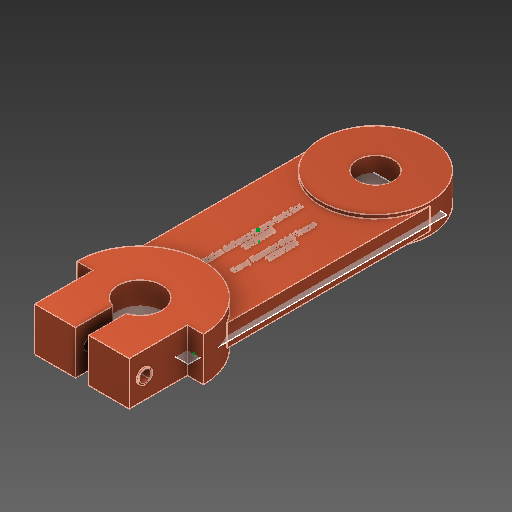
# Autodesk Inventor part: Brazo
Saved by Autodesk Inventor 2026.1 (Build 301233020, 233B)
## iProperties
Created: 2026-10-30
Part Number: Brazo
Material: Copper, Alloy
Document SubType Name: Modeling
Designer: YmCris
Density: 8.92 g/cm^3
Appearance: Copper - Satin
Author: YmCris
Autodesk Inventor part; units mm, degrees
(part 1 of 3)
ref_plane "YZ Plane" through (0, 0, 0) normal (1, 0, 0) x (0, 1, 0)
ref_plane "XZ Plane" through (0, 0, 0) normal (0, 1, 0) x (-1, 0, 0)
ref_plane "XY Plane" through (0, 0, 0) normal (0, 0, 1) x (1, 0, 0)
sketch "Sketch1" plane through (0, 0, 0) normal (0, 0, 1) x (1, 0, 0)
  point P0 (0, 0)
sketch "Sketch2" plane through (0, 0, 0) normal (0, 1, 0) x (-1, 0, 0)
  line L0 (-37.5, -80.915) -> (37.5, -80.915)
  line L1 (37.5, -80.915) -> (37.5, 80.915)
  line L2 (37.5, 80.915) -> (-37.5, 80.915)
  line L3 (-37.5, 80.915) -> (-37.5, -80.915)
  line L4 (-37.5, -80.915) -> (37.5, 80.915) construction
  line L5 (37.5, -80.915) -> (-37.5, 80.915) construction
  point P0 (0, 0)
  dimension "d4" = 75
  dimension "d5" = 161.83
  constraints: 12 end point, 2 midpoint, 2 parallel, 1 horizontal, 1 perpendicular
  measures "d4" distance of L2.end L1.end
  measures "d5" distance of L1.end L0.end
extrude "Extrusion1" add sketch "Sketch2" along normal blind 15
sketch "Sketch3" plane through (0, 15, 0) normal (0, 1, 0) x (1, 0, 0)
  point P0 (0, 0)
ref_plane "Work Plane1" through (0, 7.5, 0) normal (0, 1, 0) x (1, 0, 0)
sketch "Sketch5" plane through (0, 7.5, 0) normal (0, 1, 0) x (1, 0, 0)
  line L0 (37.5, 80.915) -> (-37.5, 80.915) projected
  circle A0 centre (0, 80.915) radius 37.5
  point P0 (0, 0)
  dimension "d10" = 75
  constraints: 1 centre point, 1 midpoint
  measures "d10" diameter of A0
extrude "Extrusion2" add sketch "Sketch5" along normal mid plane 20
sketch "Sketch6" plane through (0, 17.5, -80.915) normal (0, 1, 0) x (1, 0, 0)
  circle A0 centre (0, 0) radius 12.5
  point P0 (0, -80.915)
  dimension "d13" = 25
  constraints: 1 centre point
  measures "d13" diameter of A0
extrude "Extrusion3" cut sketch "Sketch6" against normal blind 20
sketch "Sketch7" plane through (0, 7.5, 0) normal (0, 1, 0) x (1, 0, 0)
  point P0 (0, 0)
  point P1 (-37.5, -80.915)
  point P2 (37.5, -80.915)
sketch "Sketch8" plane through (0, 7.5, 0) normal (0, 1, 0) x (1, 0, 0)
  line L0 (-37.5, -80.915) -> (37.5, -80.915) projected
  arc A0 (43.5258, -80.915) -> (-43.5258, -80.915) centre (0, -80.915) ccw
  line L1 (-43.5258, -80.915) -> (43.5258, -80.915)
  constraints: 2 end point, 2 point on circle, 1 centre point, 1 horizontal, 1 midpoint
extrude "Extrusion4" add sketch "Sketch8" along normal mid plane 30
sketch "Sketch9" plane through (0, 22.5, 0) normal (0, 1, 0) x (1, 0, 0)
  point P0 (0, 0)
sketch "Sketch10" plane through (0, 7.5, 0) normal (0, 1, 0) x (1, 0, 0)
  line L0 (43.5258, -80.915) -> (-43.5258, -80.915) projected
  line L1 (0, -80.915) -> (-32.5, -80.915)
  line L2 (-32.5, -80.915) -> (-32.5, -120.915)
  line L3 (-32.5, -120.915) -> (0, -120.915)
  line L4 (0, -120.915) -> (0, -80.915)
  line L5 (0, -80.915) -> (32.5, -80.915)
  line L6 (32.5, -80.915) -> (32.5, -120.915)
  line L7 (32.5, -120.915) -> (0, -120.915)
  point P0 (0, 0)
  dimension "d21" = 32.5
  dimension "d22" = 40
  constraints: 14 end point, 2 parallel, 2 symmetric about line, 1 horizontal, 1 midpoint, 1 perpendicular
  measures "d21" distance of L3.end L2.end
  measures "d22" distance of L2.end L1.end
extrude "Extrusion5" add sketch "Sketch10" along normal mid plane 30
sketch "Sketch11" plane through (0, 22.5, 0) normal (0, 1, 0) x (1, 0, 0)
  point P0 (0, 0)
sketch "Sketch12" plane through (0, 22.5, 0) normal (0, 1, 0) x (1, 0, 0)
  line L0 (-32.5, -120.915) -> (-32.5, -80.915) construction
  line L1 (-32.5, -120.915) -> (-4.5, -120.915) construction
  line L2 (32.5, -120.915) -> (4.5, -120.915) construction
  line L3 (32.5, -120.915) -> (60.5, -120.915) construction
  line L4 (-4.5, -120.915) -> (-4.5, -95.2241)
  line L5 (4.5, -120.915) -> (4.5, -95.2241)
  line L6 (4.5, -120.915) -> (44.5, -120.915) construction
  circle A0 centre (0, -80.915) radius 15
  line L7 (-4.5, -120.915) -> (4.5, -120.915)
  line L8 (32.5, -120.915) -> (-32.5, -120.915) projected
  point P0 (0, 0)
  point P1 (32.5, -80.915)
  dimension "d25" = 28
  dimension "d26" = 28
  dimension "d32" = 30
  constraints: 14 end point, 3 horizontal, 2 collinear, 2 point on circle, 2 vertical, 1 centre point
  measures "d25" distance of L0.start L1.end
  measures "d26" distance of L2.start L2.end
  measures "d32" diameter of A0
extrude "Extrusion6" cut sketch "Sketch12" against normal blind 30
sketch "Sketch13" plane through (32.5, -7.5, 80.915) normal (1, 0, 0) x (0, 0, -1)
  point P0 (80.915, 7.5)
sketch "Sketch14" plane through (32.5, -7.5, 80.915) normal (1, 0, 0) x (0, 0, -1)
  line L0 (0, 30) -> (-40, 30) construction
  line L1 (-40, 30) -> (-40, 15) construction
  line L2 (-40, 0) -> (-40, 30) construction
  line L3 (-40, 15) -> (0, 15) construction
  line L4 (0, 0) -> (0, 30) construction
  line L5 (-40, 0) -> (-40, 30) construction
  line L6 (-40, 15) -> (-30, 15) construction
  circle A0 centre (-30, 15) radius 5
  circle A1 centre (-30, 15) radius 4
  point P0 (80.915, 7.5)
  point P1 (0, 15)
  dimension "d35" = 15
  dimension "d36" = 40
  dimension "d37" = 10
  dimension "d39" = 10
  dimension "d40" = 8
  constraints: 6 end point, 3 midpoint, 2 centre point, 2 coincident, 1 horizontal, 1 point on line
  measures "d35" distance of L0.end L1.end
  measures "d36" distance of point (0, 15) L6.start
  measures "d37" distance of L6.start L6.end
  measures "d39" diameter of A0
  measures "d40" diameter of A1
extrude "Extrusion7" add sketch "Sketch14" along normal blind 1
sketch "Sketch15" plane through (32.5, 7.5, 110.915) normal (1, 0, 0) x (0, 0, -1)
  circle A0 centre (0, 0) radius 4
  point P0 (110.915, -7.5)
  dimension "d43" = 8
  constraints: 1 centre point
  measures "d43" diameter of A0
extrude "Extrusion8" cut sketch "Sketch15" against normal blind 65
sketch "Sketch16" plane through (-32.5, -7.5, 120.915) normal (-1, 0, 0) x (0, 0, 1)
  point P0 (-120.915, 7.5)
sketch "Sketch17" plane through (-32.5, -7.5, 120.915) normal (-1, 0, 0) x (0, 0, 1)
  circle A0 centre (-10.0974, 15.0969) radius 5
  point P0 (-120.915, 7.5)
  dimension "d46" = 10
  constraints: 1 centre point
  measures "d46" diameter of A0
extrude "Extrusion9" add sketch "Sketch17" along normal blind 1
sketch "Sketch18" plane through (-33.5, 7.5969, 110.8176) normal (-1, 0, 0) x (0, 0, 1)
  point P0 (-110.8176, -7.5969)
sketch "Sketch19" plane through (33.5, 7.5, 110.915) normal (1, 0, 0) x (0, 0, -1)
  point P0 (110.915, -7.5)
sketch "Sketch20" plane through (-33.5, 7.5969, 110.8176) normal (-1, 0, 0) x (0, 0, 1)
  circle A0 centre (0, 0) radius 4
  point P0 (-110.8176, -7.5969)
  dimension "d49" = 8
  constraints: 1 centre point
  measures "d49" diameter of A0
extrude "Extrusion10" cut sketch "Sketch20" against normal blind 69
sketch "Sketch21" plane through (0, 15, 0) normal (0, 1, 0) x (1, 0, 0)
  line L0 (-8.4274, -34.0208) -> (-8.4274, 38.1545) construction
  line L1 (-8.4274, 38.1545) -> (-19.3188, 38.1545) construction
  line L2 (-19.3188, 38.1545) -> (-19.3188, -34.0208) construction
  line L3 (-19.3188, -34.0208) -> (-8.4274, -34.0208) construction
  line L4 (7.1282, -32.5036) -> (7.1282, 37.8675) construction
  line L5 (7.1282, 37.8675) -> (43.4931, 37.8675) construction
  line L6 (43.4931, 37.8675) -> (43.4931, -32.5036) construction
  line L7 (43.4931, -32.5036) -> (7.1282, -32.5036) construction
  spline S0 degree 2 poles (-5.0391, -30.5605) (-5.0391, -30.8687) (-5.2472, -31.3902) (-5.4552, -31.5803) knots 0 0 0 1 2 2 2
  spline S1 degree 2 poles (-5.4552, -31.5803) (-5.6607, -31.7704) (-6.2773, -31.9785) (-6.678, -31.9785) knots 0 0 0 1 2 2 2
  spline S2 degree 2 poles (-6.678, -31.9785) (-7.0762, -31.9785) (-7.667, -31.7756) (-7.8854, -31.5829) knots 0 0 0 1 2 2 2
  spline S3 degree 2 poles (-7.8854, -31.5829) (-8.0986, -31.3928) (-8.3221, -30.8739) (-8.3221, -30.5528) knots 0 0 0 1 2 2 2
  spline S4 degree 2 poles (-8.3221, -30.5528) (-8.3221, -30.3935) (-8.2759, -30.1135) (-8.2399, -29.9953) knots 0 0 0 1 2 2 2
  spline S5 degree 2 poles (-8.2399, -29.9953) (-8.2065, -29.8926) (-8.1115, -29.6794) (-8.0549, -29.574) knots 0 0 0 1 2 2 2
  line L8 (-8.0549, -29.574) -> (-7.5463, -29.574)
  line L9 (-7.5463, -29.574) -> (-7.5463, -29.6074)
  spline S6 degree 2 poles (-7.5463, -29.6074) (-7.5977, -29.6639) (-7.7415, -29.8386) (-7.8109, -29.9645) knots 0 0 0 1 2 2 2
  spline S7 degree 2 poles (-7.8109, -29.9645) (-7.8777, -30.0852) (-7.9625, -30.3704) (-7.9625, -30.5553) knots 0 0 0 1 2 2 2
  spline S8 degree 2 poles (-7.9625, -30.5553) (-7.9625, -30.7583) (-7.7955, -31.1205) (-7.6362, -31.2566) knots 0 0 0 1 2 2 2
  spline S9 degree 2 poles (-7.6362, -31.2566) (-7.4744, -31.3902) (-6.9837, -31.5392) (-6.678, -31.5392) knots 0 0 0 1 2 2 2
  spline S10 degree 2 poles (-6.678, -31.5392) (-6.3518, -31.5392) (-5.8817, -31.3825) (-5.7198, -31.2464) knots 0 0 0 1 2 2 2
  spline S11 degree 2 poles (-5.7198, -31.2464) (-5.5631, -31.1128) (-5.4039, -30.7557) (-5.4039, -30.5553) knots 0 0 0 1 2 2 2
  spline S12 degree 2 poles (-5.4039, -30.5553) (-5.4039, -30.3729) (-5.4938, -30.0621) (-5.5606, -29.9414) knots 0 0 0 1 2 2 2
  spline S13 degree 2 poles (-5.5606, -29.9414) (-5.6274, -29.8258) (-5.7661, -29.6537) (-5.8149, -29.6049) knots 0 0 0 1 2 2 2
  line L10 (-5.8149, -29.6049) -> (-5.8149, -29.574)
  line L11 (-5.8149, -29.574) -> (-5.3114, -29.574)
  spline S14 degree 2 poles (-5.3114, -29.574) (-5.2626, -29.6794) (-5.1727, -29.8643) (-5.1316, -29.9953) knots 0 0 0 1 2 2 2
  spline S15 degree 2 poles (-5.1316, -29.9953) (-5.0853, -30.134) (-5.0391, -30.3704) (-5.0391, -30.5605) knots 0 0 0 1 2 2 2
  line L12 (-7.0454, -27.9505) -> (-7.0454, -27.971)
  spline S16 degree 2 poles (-7.0454, -27.971) (-7.0582, -28.0173) (-7.0634, -28.1175) (-7.0634, -28.1868) knots 0 0 0 1 2 2 2
  spline S17 degree 2 poles (-7.0634, -28.1868) (-7.0634, -28.3487) (-6.9221, -28.6672) (-6.7833, -28.8111) knots 0 0 0 1 2 2 2
  line L13 (-6.7833, -28.8111) -> (-5.0956, -28.8111)
  line L14 (-5.0956, -28.8111) -> (-5.0956, -29.2118)
  line L15 (-5.0956, -29.2118) -> (-7.4744, -29.2118)
  line L16 (-7.4744, -29.2118) -> (-7.4744, -28.8111)
  line L17 (-7.4744, -28.8111) -> (-7.1199, -28.8111)
  spline S18 degree 2 poles (-7.1199, -28.8111) (-7.3151, -28.5927) (-7.4744, -28.2665) (-7.4744, -28.1123) knots 0 0 0 1 2 2 2
  spline S19 degree 2 poles (-7.4744, -28.1123) (-7.4744, -28.0507) (-7.4692, -27.989) (-7.4615, -27.9505) knots 0 0 0 1 2 2 2
  line L18 (-7.4615, -27.9505) -> (-7.0454, -27.9505)
  line L19 (-5.0956, -27.2312) -> (-5.0956, -27.632)
  line L20 (-5.0956, -27.632) -> (-7.4744, -27.632)
  line L21 (-7.4744, -27.632) -> (-7.4744, -27.2312)
  line L22 (-7.4744, -27.2312) -> (-5.0956, -27.2312)
  line L23 (-7.87, -27.2029) -> (-7.87, -27.6576)
  line L24 (-7.87, -27.6576) -> (-8.2861, -27.6576)
  line L25 (-8.2861, -27.6576) -> (-8.2861, -27.2029)
  line L26 (-8.2861, -27.2029) -> (-7.87, -27.2029)
  spline S20 degree 2 poles (-5.0391, -26.0007) (-5.0391, -26.2396) (-5.1675, -26.6532) (-5.2395, -26.7894) knots 0 0 0 1 2 2 2
  line L27 (-5.2395, -26.7894) -> (-5.689, -26.7894)
  line L28 (-5.689, -26.7894) -> (-5.689, -26.7688)
  spline S21 degree 2 poles (-5.689, -26.7688) (-5.6479, -26.7174) (-5.5503, -26.5787) (-5.4963, -26.4631) knots 0 0 0 1 2 2 2
  spline S22 degree 2 poles (-5.4963, -26.4631) (-5.4475, -26.3629) (-5.3756, -26.1163) (-5.3756, -25.9853) knots 0 0 0 1 2 2 2
  spline S23 degree 2 poles (-5.3756, -25.9853) (-5.3756, -25.8903) (-5.4193, -25.6719) (-5.4552, -25.6205) knots 0 0 0 1 2 2 2
  spline S24 degree 2 poles (-5.4552, -25.6205) (-5.504, -25.546) (-5.6145, -25.4792) (-5.7275, -25.4792) knots 0 0 0 1 2 2 2
  spline S25 degree 2 poles (-5.7275, -25.4792) (-5.8688, -25.4792) (-6.0153, -25.6334) (-6.0641, -25.8312) knots 0 0 0 1 2 2 2
  spline S26 degree 2 poles (-6.0641, -25.8312) (-6.082, -25.9082) (-6.1334, -26.1548) (-6.1617, -26.2602) knots 0 0 0 1 2 2 2
  spline S27 degree 2 poles (-6.1617, -26.2602) (-6.2413, -26.5325) (-6.5701, -26.7791) (-6.8039, -26.7791) knots 0 0 0 1 2 2 2
  spline S28 degree 2 poles (-6.8039, -26.7791) (-7.1276, -26.7791) (-7.5309, -26.2936) (-7.5309, -25.8928) knots 0 0 0 1 2 2 2
  spline S29 degree 2 poles (-7.5309, -25.8928) (-7.5309, -25.695) (-7.4333, -25.2943) (-7.3588, -25.1581) knots 0 0 0 1 2 2 2
  line L29 (-7.3588, -25.1581) -> (-6.9298, -25.1581)
  line L30 (-6.9298, -25.1581) -> (-6.9298, -25.1787)
  spline S30 degree 2 poles (-6.9298, -25.1787) (-7.0531, -25.3328) (-7.1944, -25.7079) (-7.1944, -25.9005) knots 0 0 0 1 2 2 2
  spline S31 degree 2 poles (-7.1944, -25.9005) (-7.1944, -26.0983) (-7.0274, -26.3706) (-6.8604, -26.3706) knots 0 0 0 1 2 2 2
  spline S32 degree 2 poles (-6.8604, -26.3706) (-6.7089, -26.3706) (-6.5624, -26.2088) (-6.5162, -26.029) knots 0 0 0 1 2 2 2
  spline S33 degree 2 poles (-6.5162, -26.029) (-6.4931, -25.9416) (-6.4468, -25.7207) (-6.4186, -25.6) knots 0 0 0 1 2 2 2
  spline S34 degree 2 poles (-6.4186, -25.6) (-6.3518, -25.3379) (-6.0461, -25.0708) (-5.7815, -25.0708) knots 0 0 0 1 2 2 2
  spline S35 degree 2 poles (-5.7815, -25.0708) (-5.6274, -25.0708) (-5.3551, -25.1915) (-5.2549, -25.3097) knots 0 0 0 1 2 2 2
  spline S36 degree 2 poles (-5.2549, -25.3097) (-5.1495, -25.4356) (-5.0391, -25.7567) (-5.0391, -26.0007) knots 0 0 0 1 2 2 2
  spline S37 degree 2 poles (-5.0494, -23.979) (-5.0494, -24.3053) (-5.4218, -24.6726) (-5.8252, -24.6726) knots 0 0 0 1 2 2 2
  line L31 (-5.8252, -24.6726) -> (-7.143, -24.6726)
  line L32 (-7.143, -24.6726) -> (-7.143, -24.9423)
  line L33 (-7.143, -24.9423) -> (-7.4744, -24.9423)
  line L34 (-7.4744, -24.9423) -> (-7.4744, -24.6726)
  line L35 (-7.4744, -24.6726) -> (-8.1577, -24.6726)
  line L36 (-8.1577, -24.6726) -> (-8.1577, -24.2719)
  line L37 (-8.1577, -24.2719) -> (-7.4744, -24.2719)
  line L38 (-7.4744, -24.2719) -> (-7.4744, -23.5346)
  line L39 (-7.4744, -23.5346) -> (-7.143, -23.5346)
  line L40 (-7.143, -23.5346) -> (-7.143, -24.2719)
  line L41 (-7.143, -24.2719) -> (-6.0101, -24.2719)
  spline S38 degree 2 poles (-6.0101, -24.2719) (-5.8303, -24.2719) (-5.6325, -24.259) (-5.5477, -24.2153) knots 0 0 0 1 2 2 2
  spline S39 degree 2 poles (-5.5477, -24.2153) (-5.4732, -24.1794) (-5.3987, -24.0175) (-5.3987, -23.8788) knots 0 0 0 1 2 2 2
  spline S40 degree 2 poles (-5.3987, -23.8788) (-5.3987, -23.7812) (-5.4578, -23.5988) (-5.4758, -23.5577) knots 0 0 0 1 2 2 2
  line L42 (-5.4758, -23.5577) -> (-5.4758, -23.5346)
  line L43 (-5.4758, -23.5346) -> (-5.1161, -23.5346)
  spline S41 degree 2 poles (-5.1161, -23.5346) (-5.0853, -23.6476) (-5.0494, -23.8788) (-5.0494, -23.979) knots 0 0 0 1 2 2 2
  line L44 (-5.0956, -22.8307) -> (-5.0956, -23.2315)
  line L45 (-5.0956, -23.2315) -> (-7.4744, -23.2315)
  line L46 (-7.4744, -23.2315) -> (-7.4744, -22.8307)
  line L47 (-7.4744, -22.8307) -> (-5.0956, -22.8307)
  line L48 (-7.87, -22.8025) -> (-7.87, -23.2571)
  line L49 (-7.87, -23.2571) -> (-8.2861, -23.2571)
  line L50 (-8.2861, -23.2571) -> (-8.2861, -22.8025)
  line L51 (-8.2861, -22.8025) -> (-7.87, -22.8025)
  spline S42 degree 2 poles (-5.3473, -20.9169) (-5.3114, -20.9657) (-5.1829, -21.1301) (-5.1444, -21.2072) knots 0 0 0 1 2 2 2
  spline S43 degree 2 poles (-5.1444, -21.2072) (-5.0879, -21.3125) (-5.0288, -21.5103) (-5.0288, -21.6901) knots 0 0 0 1 2 2 2
  spline S44 degree 2 poles (-5.0288, -21.6901) (-5.0288, -21.8366) (-5.1393, -22.1012) (-5.2395, -22.2013) knots 0 0 0 1 2 2 2
  spline S45 degree 2 poles (-5.2395, -22.2013) (-5.3371, -22.2964) (-5.6248, -22.412) (-5.7841, -22.412) knots 0 0 0 1 2 2 2
  spline S46 degree 2 poles (-5.7841, -22.412) (-6.0307, -22.412) (-6.38, -22.2039) (-6.4802, -21.9778) knots 0 0 0 1 2 2 2
  spline S47 degree 2 poles (-6.4802, -21.9778) (-6.5727, -21.7775) (-6.6421, -21.2329) (-6.66, -20.9169) knots 0 0 0 1 2 2 2
  line L52 (-6.66, -20.9169) -> (-6.7371, -20.9169)
  spline S48 degree 2 poles (-6.7371, -20.9169) (-6.8758, -20.9169) (-7.0479, -21.0017) (-7.0968, -21.0787) knots 0 0 0 1 2 2 2
  spline S49 degree 2 poles (-7.0968, -21.0787) (-7.1456, -21.1558) (-7.1764, -21.3767) (-7.1764, -21.4949) knots 0 0 0 1 2 2 2
  spline S50 degree 2 poles (-7.1764, -21.4949) (-7.1764, -21.6336) (-7.0942, -22.0087) (-7.0145, -22.1962) knots 0 0 0 1 2 2 2
  line L53 (-7.0145, -22.1962) -> (-7.0145, -22.2193)
  line L54 (-7.0145, -22.2193) -> (-7.423, -22.2193)
  spline S51 degree 2 poles (-7.423, -22.2193) (-7.4538, -22.1089) (-7.5309, -21.6953) (-7.5309, -21.4923) knots 0 0 0 1 2 2 2
  spline S52 degree 2 poles (-7.5309, -21.4923) (-7.5309, -21.2457) (-7.4538, -20.9092) (-7.3536, -20.7756) knots 0 0 0 1 2 2 2
  spline S53 degree 2 poles (-7.3536, -20.7756) (-7.256, -20.6446) (-6.9452, -20.5162) (-6.7217, -20.5162) knots 0 0 0 1 2 2 2
  line L55 (-6.7217, -20.5162) -> (-5.0956, -20.5162)
  line L56 (-5.0956, -20.5162) -> (-5.0956, -20.9169)
  line L57 (-5.0956, -20.9169) -> (-5.3473, -20.9169)
  line L58 (-5.6813, -20.9169) -> (-6.3415, -20.9169)
  spline S54 degree 2 poles (-6.3415, -20.9169) (-6.3287, -21.0608) (-6.285, -21.4949) (-6.2439, -21.631) knots 0 0 0 1 2 2 2
  spline S55 degree 2 poles (-6.2439, -21.631) (-6.1951, -21.7903) (-5.9921, -21.9984) (-5.8123, -21.9984) knots 0 0 0 1 2 2 2
  spline S56 degree 2 poles (-5.8123, -21.9984) (-5.6068, -21.9984) (-5.3987, -21.7672) (-5.3987, -21.5463) knots 0 0 0 1 2 2 2
  spline S57 degree 2 poles (-5.3987, -21.5463) (-5.3987, -21.3587) (-5.5606, -21.0505) (-5.6813, -20.9169) knots 0 0 0 1 2 2 2
  line L59 (-5.0956, -18.086) -> (-5.0956, -18.4867)
  line L60 (-5.0956, -18.4867) -> (-6.452, -18.4867)
  spline S58 degree 2 poles (-6.452, -18.4867) (-6.6164, -18.4867) (-6.8989, -18.5176) (-6.9837, -18.5638) knots 0 0 0 1 2 2 2
  spline S59 degree 2 poles (-6.9837, -18.5638) (-7.0736, -18.6126) (-7.161, -18.7873) (-7.161, -18.9363) knots 0 0 0 1 2 2 2
  spline S60 degree 2 poles (-7.161, -18.9363) (-7.161, -19.0853) (-7.0017, -19.4013) (-6.8733, -19.5528) knots 0 0 0 1 2 2 2
  line L61 (-6.8733, -19.5528) -> (-5.0956, -19.5528)
  line L62 (-5.0956, -19.5528) -> (-5.0956, -19.9536)
  line L63 (-5.0956, -19.9536) -> (-7.4744, -19.9536)
  line L64 (-7.4744, -19.9536) -> (-7.4744, -19.5528)
  line L65 (-7.4744, -19.5528) -> (-7.2098, -19.5528)
  spline S61 degree 2 poles (-7.2098, -19.5528) (-7.3716, -19.373) (-7.5412, -19.0262) (-7.5412, -18.831) knots 0 0 0 1 2 2 2
  spline S62 degree 2 poles (-7.5412, -18.831) (-7.5412, -18.4816) (-7.0788, -18.086) (-6.6395, -18.086) knots 0 0 0 1 2 2 2
  line L66 (-6.6395, -18.086) -> (-5.0956, -18.086)
  spline S63 degree 2 poles (-5.0339, -14.803) (-5.0339, -15.1395) (-5.2395, -15.6969) (-5.4475, -15.8973) knots 0 0 0 1 2 2 2
  spline S64 degree 2 poles (-5.4475, -15.8973) (-5.6582, -16.0977) (-6.2798, -16.3109) (-6.6832, -16.3109) knots 0 0 0 1 2 2 2
  spline S65 degree 2 poles (-6.6832, -16.3109) (-7.0659, -16.3109) (-7.6722, -16.0951) (-7.888, -15.8947) knots 0 0 0 1 2 2 2
  spline S66 degree 2 poles (-7.888, -15.8947) (-8.096, -15.7021) (-8.3221, -15.1369) (-8.3221, -14.8004) knots 0 0 0 1 2 2 2
  spline S67 degree 2 poles (-8.3221, -14.8004) (-8.3221, -14.6385) (-8.2759, -14.3457) (-8.2348, -14.2121) knots 0 0 0 1 2 2 2
  spline S68 degree 2 poles (-8.2348, -14.2121) (-8.2039, -14.1042) (-8.0909, -13.8422) (-8.0498, -13.7626) knots 0 0 0 1 2 2 2
  line L67 (-8.0498, -13.7626) -> (-7.5412, -13.7626)
  line L68 (-7.5412, -13.7626) -> (-7.5412, -13.7985)
  spline S69 degree 2 poles (-7.5412, -13.7985) (-7.6105, -13.8782) (-7.7364, -14.0451) (-7.8083, -14.1993) knots 0 0 0 1 2 2 2
  spline S70 degree 2 poles (-7.8083, -14.1993) (-7.8726, -14.3277) (-7.9573, -14.6591) (-7.9573, -14.8492) knots 0 0 0 1 2 2 2
  spline S71 degree 2 poles (-7.9573, -14.8492) (-7.9573, -15.3065) (-7.2689, -15.8716) (-6.696, -15.8716) knots 0 0 0 1 2 2 2
  spline S72 degree 2 poles (-6.696, -15.8716) (-6.3775, -15.8716) (-5.8997, -15.7226) (-5.7352, -15.5813) knots 0 0 0 1 2 2 2
  spline S73 degree 2 poles (-5.7352, -15.5813) (-5.5708, -15.4452) (-5.3987, -15.0598) (-5.3987, -14.8184) knots 0 0 0 1 2 2 2
  spline S74 degree 2 poles (-5.3987, -14.8184) (-5.3987, -14.6411) (-5.4501, -14.2866) (-5.5015, -14.1659) knots 0 0 0 1 2 2 2
  line L69 (-5.5015, -14.1659) -> (-6.321, -14.1659)
  line L70 (-6.321, -14.1659) -> (-6.321, -14.9006)
  line L71 (-6.321, -14.9006) -> (-6.6909, -14.9006)
  line L72 (-6.6909, -14.9006) -> (-6.6909, -13.7497)
  line L73 (-6.6909, -13.7497) -> (-5.3062, -13.7497)
  spline S75 degree 2 poles (-5.3062, -13.7497) (-5.2703, -13.8294) (-5.1598, -14.1017) (-5.1264, -14.2173) knots 0 0 0 1 2 2 2
  spline S76 degree 2 poles (-5.1264, -14.2173) (-5.0802, -14.374) (-5.0339, -14.6257) (-5.0339, -14.803) knots 0 0 0 1 2 2 2
  spline S77 degree 2 poles (-5.0416, -12.2187) (-5.0416, -12.789) (-5.6813, -13.4158) (-6.2721, -13.4158) knots 0 0 0 1 2 2 2
  spline S78 degree 2 poles (-6.2721, -13.4158) (-6.8527, -13.4158) (-7.5412, -12.8069) (-7.5412, -12.3163) knots 0 0 0 1 2 2 2
  spline S79 degree 2 poles (-7.5412, -12.3163) (-7.5412, -12.0954) (-7.4127, -11.7537) (-7.2766, -11.6278) knots 0 0 0 1 2 2 2
  spline S80 degree 2 poles (-7.2766, -11.6278) (-7.1404, -11.4994) (-6.7474, -11.3632) (-6.4622, -11.3632) knots 0 0 0 1 2 2 2
  line L74 (-6.4622, -11.3632) -> (-6.2439, -11.3632)
  line L75 (-6.2439, -11.3632) -> (-6.2439, -13.0099)
  spline S81 degree 2 poles (-6.2439, -13.0099) (-5.8303, -13.0099) (-5.391, -12.5937) (-5.391, -12.2238) knots 0 0 0 1 2 2 2
  spline S82 degree 2 poles (-5.391, -12.2238) (-5.391, -12.0928) (-5.4501, -11.8385) (-5.4963, -11.7357) knots 0 0 0 1 2 2 2
  spline S83 degree 2 poles (-5.4963, -11.7357) (-5.5477, -11.6278) (-5.6376, -11.4788) (-5.6787, -11.43) knots 0 0 0 1 2 2 2
  line L76 (-5.6787, -11.43) -> (-5.6787, -11.4069)
  line L77 (-5.6787, -11.4069) -> (-5.242, -11.4069)
  spline S84 degree 2 poles (-5.242, -11.4069) (-5.2138, -11.4763) (-5.1316, -11.6869) (-5.1084, -11.7691) knots 0 0 0 1 2 2 2
  spline S85 degree 2 poles (-5.1084, -11.7691) (-5.075, -11.8847) (-5.0416, -12.0748) (-5.0416, -12.2187) knots 0 0 0 1 2 2 2
  spline S86 degree 2 poles (-6.5496, -11.7537) (-6.7114, -11.7588) (-6.9478, -11.8256) (-7.0274, -11.8898) knots 0 0 0 1 2 2 2
  spline S87 degree 2 poles (-7.0274, -11.8898) (-7.1173, -11.9592) (-7.2124, -12.1776) (-7.2124, -12.3394) knots 0 0 0 1 2 2 2
  spline S88 degree 2 poles (-7.2124, -12.3394) (-7.2124, -12.4987) (-7.1173, -12.7222) (-7.0248, -12.8146) knots 0 0 0 1 2 2 2
  spline S89 degree 2 poles (-7.0248, -12.8146) (-6.9298, -12.9046) (-6.7011, -12.997) (-6.5496, -13.0099) knots 0 0 0 1 2 2 2
  line L78 (-6.5496, -13.0099) -> (-6.5496, -11.7537)
  line L79 (-8.0216, -9.7063) -> (-8.0216, -9.7268)
  spline S90 degree 2 poles (-8.0216, -9.7268) (-8.0421, -9.7808) (-8.0781, -9.9812) (-8.0781, -10.0608) knots 0 0 0 1 2 2 2
  spline S91 degree 2 poles (-8.0781, -10.0608) (-8.0781, -10.3126) (-7.852, -10.5283) (-7.554, -10.5283) knots 0 0 0 1 2 2 2
  line L80 (-7.554, -10.5283) -> (-7.4744, -10.5283)
  line L81 (-7.4744, -10.5283) -> (-7.4744, -9.8656)
  line L82 (-7.4744, -9.8656) -> (-7.143, -9.8656)
  line L83 (-7.143, -9.8656) -> (-7.143, -10.5155)
  line L84 (-7.143, -10.5155) -> (-5.0956, -10.5155)
  line L85 (-5.0956, -10.5155) -> (-5.0956, -10.9162)
  line L86 (-5.0956, -10.9162) -> (-7.143, -10.9162)
  line L87 (-7.143, -10.9162) -> (-7.143, -11.186)
  line L88 (-7.143, -11.186) -> (-7.4744, -11.186)
  line L89 (-7.4744, -11.186) -> (-7.4744, -10.9162)
  line L90 (-7.4744, -10.9162) -> (-7.554, -10.9162)
  spline S92 degree 2 poles (-7.554, -10.9162) (-7.9804, -10.9162) (-8.4274, -10.5026) (-8.4274, -10.1173) knots 0 0 0 1 2 2 2
  spline S93 degree 2 poles (-8.4274, -10.1173) (-8.4274, -10.0069) (-8.4043, -9.7936) (-8.3889, -9.7063) knots 0 0 0 1 2 2 2
  line L91 (-8.3889, -9.7063) -> (-8.0216, -9.7063)
  line L92 (-8.0216, -8.3191) -> (-8.0216, -8.3397)
  spline S94 degree 2 poles (-8.0216, -8.3397) (-8.0421, -8.3936) (-8.0781, -8.594) (-8.0781, -8.6736) knots 0 0 0 1 2 2 2
  spline S95 degree 2 poles (-8.0781, -8.6736) (-8.0781, -8.9254) (-7.852, -9.1411) (-7.554, -9.1411) knots 0 0 0 1 2 2 2
  line L93 (-7.554, -9.1411) -> (-7.4744, -9.1411)
  line L94 (-7.4744, -9.1411) -> (-7.4744, -8.4784)
  line L95 (-7.4744, -8.4784) -> (-7.143, -8.4784)
  line L96 (-7.143, -8.4784) -> (-7.143, -9.1283)
  line L97 (-7.143, -9.1283) -> (-5.0956, -9.1283)
  line L98 (-5.0956, -9.1283) -> (-5.0956, -9.529)
  line L99 (-5.0956, -9.529) -> (-7.143, -9.529)
  line L100 (-7.143, -9.529) -> (-7.143, -9.7988)
  line L101 (-7.143, -9.7988) -> (-7.4744, -9.7988)
  line L102 (-7.4744, -9.7988) -> (-7.4744, -9.529)
  line L103 (-7.4744, -9.529) -> (-7.554, -9.529)
  spline S96 degree 2 poles (-7.554, -9.529) (-7.9804, -9.529) (-8.4274, -9.1155) (-8.4274, -8.7301) knots 0 0 0 1 2 2 2
  spline S97 degree 2 poles (-8.4274, -8.7301) (-8.4274, -8.6197) (-8.4043, -8.4064) (-8.3889, -8.3191) knots 0 0 0 1 2 2 2
  line L104 (-8.3889, -8.3191) -> (-8.0216, -8.3191)
  spline S98 degree 2 poles (-5.0416, -7.1503) (-5.0416, -7.7206) (-5.6813, -8.3474) (-6.2721, -8.3474) knots 0 0 0 1 2 2 2
  spline S99 degree 2 poles (-6.2721, -8.3474) (-6.8527, -8.3474) (-7.5412, -7.7385) (-7.5412, -7.2479) knots 0 0 0 1 2 2 2
  spline S100 degree 2 poles (-7.5412, -7.2479) (-7.5412, -7.027) (-7.4127, -6.6853) (-7.2766, -6.5594) knots 0 0 0 1 2 2 2
  spline S101 degree 2 poles (-7.2766, -6.5594) (-7.1404, -6.431) (-6.7474, -6.2948) (-6.4622, -6.2948) knots 0 0 0 1 2 2 2
  line L105 (-6.4622, -6.2948) -> (-6.2439, -6.2948)
  line L106 (-6.2439, -6.2948) -> (-6.2439, -7.9415)
  spline S102 degree 2 poles (-6.2439, -7.9415) (-5.8303, -7.9415) (-5.391, -7.5253) (-5.391, -7.1554) knots 0 0 0 1 2 2 2
  spline S103 degree 2 poles (-5.391, -7.1554) (-5.391, -7.0244) (-5.4501, -6.7701) (-5.4963, -6.6673) knots 0 0 0 1 2 2 2
  spline S104 degree 2 poles (-5.4963, -6.6673) (-5.5477, -6.5594) (-5.6376, -6.4104) (-5.6787, -6.3616) knots 0 0 0 1 2 2 2
  line L107 (-5.6787, -6.3616) -> (-5.6787, -6.3385)
  line L108 (-5.6787, -6.3385) -> (-5.242, -6.3385)
  spline S105 degree 2 poles (-5.242, -6.3385) (-5.2138, -6.4079) (-5.1316, -6.6185) (-5.1084, -6.7007) knots 0 0 0 1 2 2 2
  spline S106 degree 2 poles (-5.1084, -6.7007) (-5.075, -6.8163) (-5.0416, -7.0064) (-5.0416, -7.1503) knots 0 0 0 1 2 2 2
  spline S107 degree 2 poles (-6.5496, -6.6853) (-6.7114, -6.6904) (-6.9478, -6.7572) (-7.0274, -6.8214) knots 0 0 0 1 2 2 2
  spline S108 degree 2 poles (-7.0274, -6.8214) (-7.1173, -6.8908) (-7.2124, -7.1092) (-7.2124, -7.271) knots 0 0 0 1 2 2 2
  spline S109 degree 2 poles (-7.2124, -7.271) (-7.2124, -7.4303) (-7.1173, -7.6538) (-7.0248, -7.7462) knots 0 0 0 1 2 2 2
  spline S110 degree 2 poles (-7.0248, -7.7462) (-6.9298, -7.8362) (-6.7011, -7.9286) (-6.5496, -7.9415) knots 0 0 0 1 2 2 2
  line L109 (-6.5496, -7.9415) -> (-6.5496, -6.6853)
  line L110 (-7.0454, -4.6276) -> (-7.0454, -4.6482)
  spline S111 degree 2 poles (-7.0454, -4.6482) (-7.0582, -4.6944) (-7.0634, -4.7946) (-7.0634, -4.864) knots 0 0 0 1 2 2 2
  spline S112 degree 2 poles (-7.0634, -4.864) (-7.0634, -5.0258) (-6.9221, -5.3443) (-6.7833, -5.4882) knots 0 0 0 1 2 2 2
  line L111 (-6.7833, -5.4882) -> (-5.0956, -5.4882)
  line L112 (-5.0956, -5.4882) -> (-5.0956, -5.8889)
  line L113 (-5.0956, -5.8889) -> (-7.4744, -5.8889)
  line L114 (-7.4744, -5.8889) -> (-7.4744, -5.4882)
  line L115 (-7.4744, -5.4882) -> (-7.1199, -5.4882)
  spline S113 degree 2 poles (-7.1199, -5.4882) (-7.3151, -5.2698) (-7.4744, -4.9436) (-7.4744, -4.7895) knots 0 0 0 1 2 2 2
  spline S114 degree 2 poles (-7.4744, -4.7895) (-7.4744, -4.7278) (-7.4692, -4.6662) (-7.4615, -4.6276) knots 0 0 0 1 2 2 2
  line L116 (-7.4615, -4.6276) -> (-7.0454, -4.6276)
  spline S115 degree 2 poles (-5.0391, -3.6746) (-5.0391, -3.9135) (-5.1675, -4.3271) (-5.2395, -4.4632) knots 0 0 0 1 2 2 2
  line L117 (-5.2395, -4.4632) -> (-5.689, -4.4632)
  line L118 (-5.689, -4.4632) -> (-5.689, -4.4427)
  spline S116 degree 2 poles (-5.689, -4.4427) (-5.6479, -4.3913) (-5.5503, -4.2526) (-5.4963, -4.137) knots 0 0 0 1 2 2 2
  spline S117 degree 2 poles (-5.4963, -4.137) (-5.4475, -4.0368) (-5.3756, -3.7902) (-5.3756, -3.6591) knots 0 0 0 1 2 2 2
  spline S118 degree 2 poles (-5.3756, -3.6591) (-5.3756, -3.5641) (-5.4193, -3.3457) (-5.4552, -3.2944) knots 0 0 0 1 2 2 2
  spline S119 degree 2 poles (-5.4552, -3.2944) (-5.504, -3.2199) (-5.6145, -3.1531) (-5.7275, -3.1531) knots 0 0 0 1 2 2 2
  spline S120 degree 2 poles (-5.7275, -3.1531) (-5.8688, -3.1531) (-6.0153, -3.3072) (-6.0641, -3.505) knots 0 0 0 1 2 2 2
  spline S121 degree 2 poles (-6.0641, -3.505) (-6.082, -3.5821) (-6.1334, -3.8287) (-6.1617, -3.934) knots 0 0 0 1 2 2 2
  spline S122 degree 2 poles (-6.1617, -3.934) (-6.2413, -4.2063) (-6.5701, -4.4529) (-6.8039, -4.4529) knots 0 0 0 1 2 2 2
  spline S123 degree 2 poles (-6.8039, -4.4529) (-7.1276, -4.4529) (-7.5309, -3.9674) (-7.5309, -3.5667) knots 0 0 0 1 2 2 2
  spline S124 degree 2 poles (-7.5309, -3.5667) (-7.5309, -3.3689) (-7.4333, -2.9681) (-7.3588, -2.832) knots 0 0 0 1 2 2 2
  line L119 (-7.3588, -2.832) -> (-6.9298, -2.832)
  line L120 (-6.9298, -2.832) -> (-6.9298, -2.8525)
  spline S125 degree 2 poles (-6.9298, -2.8525) (-7.0531, -3.0067) (-7.1944, -3.3817) (-7.1944, -3.5744) knots 0 0 0 1 2 2 2
  spline S126 degree 2 poles (-7.1944, -3.5744) (-7.1944, -3.7722) (-7.0274, -4.0445) (-6.8604, -4.0445) knots 0 0 0 1 2 2 2
  spline S127 degree 2 poles (-6.8604, -4.0445) (-6.7089, -4.0445) (-6.5624, -3.8826) (-6.5162, -3.7028) knots 0 0 0 1 2 2 2
  spline S128 degree 2 poles (-6.5162, -3.7028) (-6.4931, -3.6155) (-6.4468, -3.3946) (-6.4186, -3.2738) knots 0 0 0 1 2 2 2
  spline S129 degree 2 poles (-6.4186, -3.2738) (-6.3518, -3.0118) (-6.0461, -2.7446) (-5.7815, -2.7446) knots 0 0 0 1 2 2 2
  spline S130 degree 2 poles (-5.7815, -2.7446) (-5.6274, -2.7446) (-5.3551, -2.8654) (-5.2549, -2.9835) knots 0 0 0 1 2 2 2
  spline S131 degree 2 poles (-5.2549, -2.9835) (-5.1495, -3.1094) (-5.0391, -3.4305) (-5.0391, -3.6746) knots 0 0 0 1 2 2 2
  spline S132 degree 2 poles (-6.285, -0.4172) (-5.6839, -0.4172) (-5.0288, -0.9952) (-5.0288, -1.4782) knots 0 0 0 1 2 2 2
  spline S133 degree 2 poles (-5.0288, -1.4782) (-5.0288, -1.974) (-5.7044, -2.5417) (-6.285, -2.5417) knots 0 0 0 1 2 2 2
  spline S134 degree 2 poles (-6.285, -2.5417) (-6.881, -2.5417) (-7.5412, -1.956) (-7.5412, -1.4782) knots 0 0 0 1 2 2 2
  spline S135 degree 2 poles (-7.5412, -1.4782) (-7.5412, -0.9952) (-6.8835, -0.4172) (-6.285, -0.4172) knots 0 0 0 1 2 2 2
  spline S136 degree 2 poles (-6.285, -0.8308) (-6.7474, -0.8308) (-7.1969, -1.1673) (-7.1969, -1.4782) knots 0 0 0 1 2 2 2
  spline S137 degree 2 poles (-7.1969, -1.4782) (-7.1969, -1.789) (-6.7474, -2.1281) (-6.285, -2.1281) knots 0 0 0 1 2 2 2
  spline S138 degree 2 poles (-6.285, -2.1281) (-5.8354, -2.1281) (-5.373, -1.789) (-5.373, -1.4782) knots 0 0 0 1 2 2 2
  spline S139 degree 2 poles (-5.373, -1.4782) (-5.373, -1.1699) (-5.8277, -0.8308) (-6.285, -0.8308) knots 0 0 0 1 2 2 2
  line L121 (-5.0956, 1.8614) -> (-5.0956, 1.4606)
  line L122 (-5.0956, 1.4606) -> (-6.452, 1.4606)
  spline S140 degree 2 poles (-6.452, 1.4606) (-6.6164, 1.4606) (-6.8989, 1.4298) (-6.9837, 1.3836) knots 0 0 0 1 2 2 2
  spline S141 degree 2 poles (-6.9837, 1.3836) (-7.0736, 1.3348) (-7.161, 1.1601) (-7.161, 1.0111) knots 0 0 0 1 2 2 2
  spline S142 degree 2 poles (-7.161, 1.0111) (-7.161, 0.8621) (-7.0017, 0.5461) (-6.8733, 0.3945) knots 0 0 0 1 2 2 2
  line L123 (-6.8733, 0.3945) -> (-5.0956, 0.3945)
  line L124 (-5.0956, 0.3945) -> (-5.0956, -0.0062)
  line L125 (-5.0956, -0.0062) -> (-7.4744, -0.0062)
  line L126 (-7.4744, -0.0062) -> (-7.4744, 0.3945)
  line L127 (-7.4744, 0.3945) -> (-7.2098, 0.3945)
  spline S143 degree 2 poles (-7.2098, 0.3945) (-7.3716, 0.5744) (-7.5412, 0.9212) (-7.5412, 1.1164) knots 0 0 0 1 2 2 2
  spline S144 degree 2 poles (-7.5412, 1.1164) (-7.5412, 1.4658) (-7.0788, 1.8614) (-6.6395, 1.8614) knots 0 0 0 1 2 2 2
  line L128 (-6.6395, 1.8614) -> (-5.0956, 1.8614)
  spline S145 degree 2 poles (-5.0391, 4.7) (-5.0391, 4.3558) (-5.1829, 3.8728) (-5.2857, 3.6596) knots 0 0 0 1 2 2 2
  line L129 (-5.2857, 3.6596) -> (-5.8149, 3.6596)
  line L130 (-5.8149, 3.6596) -> (-5.8149, 3.6904)
  spline S146 degree 2 poles (-5.8149, 3.6904) (-5.6196, 3.8985) (-5.4039, 4.4251) (-5.4039, 4.6692) knots 0 0 0 1 2 2 2
  spline S147 degree 2 poles (-5.4039, 4.6692) (-5.4039, 5.0185) (-5.6941, 5.3756) (-5.933, 5.3756) knots 0 0 0 1 2 2 2
  spline S148 degree 2 poles (-5.933, 5.3756) (-6.1231, 5.3756) (-6.3595, 5.1881) (-6.4186, 4.9851) knots 0 0 0 1 2 2 2
  spline S149 degree 2 poles (-6.4186, 4.9851) (-6.4597, 4.8387) (-6.5162, 4.5947) (-6.5624, 4.4123) knots 0 0 0 1 2 2 2
  spline S150 degree 2 poles (-6.5624, 4.4123) (-6.6061, 4.2479) (-6.7371, 3.9884) (-6.8424, 3.8882) knots 0 0 0 1 2 2 2
  spline S151 degree 2 poles (-6.8424, 3.8882) (-6.9478, 3.7906) (-7.2303, 3.6827) (-7.4153, 3.6827) knots 0 0 0 1 2 2 2
  spline S152 degree 2 poles (-7.4153, 3.6827) (-7.8006, 3.6827) (-8.3221, 4.2838) (-8.3221, 4.7488) knots 0 0 0 1 2 2 2
  spline S153 degree 2 poles (-8.3221, 4.7488) (-8.3221, 5.016) (-8.2168, 5.4886) (-8.1166, 5.6916) knots 0 0 0 1 2 2 2
  line L131 (-8.1166, 5.6916) -> (-7.6131, 5.6916)
  line L132 (-7.6131, 5.6916) -> (-7.6131, 5.6608)
  spline S154 degree 2 poles (-7.6131, 5.6608) (-7.7518, 5.5092) (-7.9573, 5.0365) (-7.9573, 4.7771) knots 0 0 0 1 2 2 2
  spline S155 degree 2 poles (-7.9573, 4.7771) (-7.9573, 4.4842) (-7.6825, 4.122) (-7.459, 4.122) knots 0 0 0 1 2 2 2
  spline S156 degree 2 poles (-7.459, 4.122) (-7.2586, 4.122) (-7.0197, 4.3352) (-6.9657, 4.5356) knots 0 0 0 1 2 2 2
  spline S157 degree 2 poles (-6.9657, 4.5356) (-6.9298, 4.6692) (-6.8373, 5.0571) (-6.7988, 5.1855) knots 0 0 0 1 2 2 2
  spline S158 degree 2 poles (-6.7988, 5.1855) (-6.6986, 5.5118) (-6.2953, 5.8149) (-5.9998, 5.8149) knots 0 0 0 1 2 2 2
  spline S159 degree 2 poles (-5.9998, 5.8149) (-5.8123, 5.8149) (-5.4527, 5.6633) (-5.3268, 5.5272) knots 0 0 0 1 2 2 2
  spline S160 degree 2 poles (-5.3268, 5.5272) (-5.1881, 5.3756) (-5.0391, 4.9903) (-5.0391, 4.7) knots 0 0 0 1 2 2 2
  spline S161 degree 2 poles (-5.0494, 6.9324) (-5.0494, 6.6061) (-5.4218, 6.2388) (-5.8252, 6.2388) knots 0 0 0 1 2 2 2
  line L133 (-5.8252, 6.2388) -> (-7.143, 6.2388)
  line L134 (-7.143, 6.2388) -> (-7.143, 5.969)
  line L135 (-7.143, 5.969) -> (-7.4744, 5.969)
  line L136 (-7.4744, 5.969) -> (-7.4744, 6.2388)
  line L137 (-7.4744, 6.2388) -> (-8.1577, 6.2388)
  line L138 (-8.1577, 6.2388) -> (-8.1577, 6.6395)
  line L139 (-8.1577, 6.6395) -> (-7.4744, 6.6395)
  line L140 (-7.4744, 6.6395) -> (-7.4744, 7.3768)
  line L141 (-7.4744, 7.3768) -> (-7.143, 7.3768)
  line L142 (-7.143, 7.3768) -> (-7.143, 6.6395)
  line L143 (-7.143, 6.6395) -> (-6.0101, 6.6395)
  spline S162 degree 2 poles (-6.0101, 6.6395) (-5.8303, 6.6395) (-5.6325, 6.6523) (-5.5477, 6.696) knots 0 0 0 1 2 2 2
  spline S163 degree 2 poles (-5.5477, 6.696) (-5.4732, 6.732) (-5.3987, 6.8938) (-5.3987, 7.0325) knots 0 0 0 1 2 2 2
  spline S164 degree 2 poles (-5.3987, 7.0325) (-5.3987, 7.1302) (-5.4578, 7.3125) (-5.4758, 7.3536) knots 0 0 0 1 2 2 2
  line L144 (-5.4758, 7.3536) -> (-5.4758, 7.3768)
  line L145 (-5.4758, 7.3768) -> (-5.1161, 7.3768)
  spline S165 degree 2 poles (-5.1161, 7.3768) (-5.0853, 7.2637) (-5.0494, 7.0325) (-5.0494, 6.9324) knots 0 0 0 1 2 2 2
  spline S166 degree 2 poles (-5.0416, 8.7049) (-5.0416, 8.1346) (-5.6813, 7.5078) (-6.2721, 7.5078) knots 0 0 0 1 2 2 2
  spline S167 degree 2 poles (-6.2721, 7.5078) (-6.8527, 7.5078) (-7.5412, 8.1166) (-7.5412, 8.6073) knots 0 0 0 1 2 2 2
  spline S168 degree 2 poles (-7.5412, 8.6073) (-7.5412, 8.8282) (-7.4127, 9.1698) (-7.2766, 9.2957) knots 0 0 0 1 2 2 2
  spline S169 degree 2 poles (-7.2766, 9.2957) (-7.1404, 9.4242) (-6.7474, 9.5603) (-6.4622, 9.5603) knots 0 0 0 1 2 2 2
  line L146 (-6.4622, 9.5603) -> (-6.2439, 9.5603)
  line L147 (-6.2439, 9.5603) -> (-6.2439, 7.9137)
  spline S170 degree 2 poles (-6.2439, 7.9137) (-5.8303, 7.9137) (-5.391, 8.3298) (-5.391, 8.6997) knots 0 0 0 1 2 2 2
  spline S171 degree 2 poles (-5.391, 8.6997) (-5.391, 8.8308) (-5.4501, 9.0851) (-5.4963, 9.1878) knots 0 0 0 1 2 2 2
  spline S172 degree 2 poles (-5.4963, 9.1878) (-5.5477, 9.2957) (-5.6376, 9.4447) (-5.6787, 9.4935) knots 0 0 0 1 2 2 2
  line L148 (-5.6787, 9.4935) -> (-5.6787, 9.5166)
  line L149 (-5.6787, 9.5166) -> (-5.242, 9.5166)
  spline S173 degree 2 poles (-5.242, 9.5166) (-5.2138, 9.4473) (-5.1316, 9.2366) (-5.1084, 9.1544) knots 0 0 0 1 2 2 2
  spline S174 degree 2 poles (-5.1084, 9.1544) (-5.075, 9.0388) (-5.0416, 8.8487) (-5.0416, 8.7049) knots 0 0 0 1 2 2 2
  spline S175 degree 2 poles (-6.5496, 9.1698) (-6.7114, 9.1647) (-6.9478, 9.0979) (-7.0274, 9.0337) knots 0 0 0 1 2 2 2
  spline S176 degree 2 poles (-7.0274, 9.0337) (-7.1173, 8.9643) (-7.2124, 8.746) (-7.2124, 8.5841) knots 0 0 0 1 2 2 2
  spline S177 degree 2 poles (-7.2124, 8.5841) (-7.2124, 8.4249) (-7.1173, 8.2014) (-7.0248, 8.1089) knots 0 0 0 1 2 2 2
  spline S178 degree 2 poles (-7.0248, 8.1089) (-6.9298, 8.019) (-6.7011, 7.9265) (-6.5496, 7.9137) knots 0 0 0 1 2 2 2
  line L150 (-6.5496, 7.9137) -> (-6.5496, 9.1698)
  line L151 (-7.4744, 11.8338) -> (-5.0956, 10.9372)
  line L152 (-5.0956, 10.9372) -> (-5.0956, 10.5776)
  line L153 (-5.0956, 10.5776) -> (-7.4744, 9.6888)
  line L154 (-7.4744, 9.6888) -> (-7.4744, 10.1229)
  line L155 (-7.4744, 10.1229) -> (-5.6428, 10.7728)
  line L156 (-5.6428, 10.7728) -> (-7.4744, 11.4176)
  line L157 (-7.4744, 11.4176) -> (-7.4744, 11.8338)
  spline S179 degree 2 poles (-5.0416, 13.1696) (-5.0416, 12.5993) (-5.6813, 11.9725) (-6.2721, 11.9725) knots 0 0 0 1 2 2 2
  spline S180 degree 2 poles (-6.2721, 11.9725) (-6.8527, 11.9725) (-7.5412, 12.5813) (-7.5412, 13.072) knots 0 0 0 1 2 2 2
  spline S181 degree 2 poles (-7.5412, 13.072) (-7.5412, 13.2929) (-7.4127, 13.6346) (-7.2766, 13.7604) knots 0 0 0 1 2 2 2
  spline S182 degree 2 poles (-7.2766, 13.7604) (-7.1404, 13.8889) (-6.7474, 14.025) (-6.4622, 14.025) knots 0 0 0 1 2 2 2
  line L158 (-6.4622, 14.025) -> (-6.2439, 14.025)
  line L159 (-6.2439, 14.025) -> (-6.2439, 12.3784)
  spline S183 degree 2 poles (-6.2439, 12.3784) (-5.8303, 12.3784) (-5.391, 12.7945) (-5.391, 13.1645) knots 0 0 0 1 2 2 2
  spline S184 degree 2 poles (-5.391, 13.1645) (-5.391, 13.2955) (-5.4501, 13.5498) (-5.4963, 13.6525) knots 0 0 0 1 2 2 2
  spline S185 degree 2 poles (-5.4963, 13.6525) (-5.5477, 13.7604) (-5.6376, 13.9094) (-5.6787, 13.9582) knots 0 0 0 1 2 2 2
  line L160 (-5.6787, 13.9582) -> (-5.6787, 13.9814)
  line L161 (-5.6787, 13.9814) -> (-5.242, 13.9814)
  spline S186 degree 2 poles (-5.242, 13.9814) (-5.2138, 13.912) (-5.1316, 13.7014) (-5.1084, 13.6191) knots 0 0 0 1 2 2 2
  spline S187 degree 2 poles (-5.1084, 13.6191) (-5.075, 13.5036) (-5.0416, 13.3135) (-5.0416, 13.1696) knots 0 0 0 1 2 2 2
  spline S188 degree 2 poles (-6.5496, 13.6346) (-6.7114, 13.6294) (-6.9478, 13.5626) (-7.0274, 13.4984) knots 0 0 0 1 2 2 2
  spline S189 degree 2 poles (-7.0274, 13.4984) (-7.1173, 13.4291) (-7.2124, 13.2107) (-7.2124, 13.0489) knots 0 0 0 1 2 2 2
  spline S190 degree 2 poles (-7.2124, 13.0489) (-7.2124, 12.8896) (-7.1173, 12.6661) (-7.0248, 12.5736) knots 0 0 0 1 2 2 2
  spline S191 degree 2 poles (-7.0248, 12.5736) (-6.9298, 12.4837) (-6.7011, 12.3912) (-6.5496, 12.3784) knots 0 0 0 1 2 2 2
  line L162 (-6.5496, 12.3784) -> (-6.5496, 13.6346)
  line L163 (-5.0956, 16.2985) -> (-5.0956, 15.8977)
  line L164 (-5.0956, 15.8977) -> (-6.452, 15.8977)
  spline S192 degree 2 poles (-6.452, 15.8977) (-6.6164, 15.8977) (-6.8989, 15.8669) (-6.9837, 15.8207) knots 0 0 0 1 2 2 2
  spline S193 degree 2 poles (-6.9837, 15.8207) (-7.0736, 15.7719) (-7.161, 15.5972) (-7.161, 15.4482) knots 0 0 0 1 2 2 2
  spline S194 degree 2 poles (-7.161, 15.4482) (-7.161, 15.2992) (-7.0017, 14.9832) (-6.8733, 14.8317) knots 0 0 0 1 2 2 2
  line L165 (-6.8733, 14.8317) -> (-5.0956, 14.8317)
  line L166 (-5.0956, 14.8317) -> (-5.0956, 14.4309)
  line L167 (-5.0956, 14.4309) -> (-7.4744, 14.4309)
  line L168 (-7.4744, 14.4309) -> (-7.4744, 14.8317)
  line L169 (-7.4744, 14.8317) -> (-7.2098, 14.8317)
  spline S195 degree 2 poles (-7.2098, 14.8317) (-7.3716, 15.0115) (-7.5412, 15.3583) (-7.5412, 15.5535) knots 0 0 0 1 2 2 2
  spline S196 degree 2 poles (-7.5412, 15.5535) (-7.5412, 15.9029) (-7.0788, 16.2985) (-6.6395, 16.2985) knots 0 0 0 1 2 2 2
  line L170 (-6.6395, 16.2985) -> (-5.0956, 16.2985)
  spline S197 degree 2 poles (-5.0391, 19.1371) (-5.0391, 18.7929) (-5.1829, 18.3099) (-5.2857, 18.0967) knots 0 0 0 1 2 2 2
  line L171 (-5.2857, 18.0967) -> (-5.8149, 18.0967)
  line L172 (-5.8149, 18.0967) -> (-5.8149, 18.1275)
  spline S198 degree 2 poles (-5.8149, 18.1275) (-5.6196, 18.3356) (-5.4039, 18.8622) (-5.4039, 19.1063) knots 0 0 0 1 2 2 2
  spline S199 degree 2 poles (-5.4039, 19.1063) (-5.4039, 19.4556) (-5.6941, 19.8127) (-5.933, 19.8127) knots 0 0 0 1 2 2 2
  spline S200 degree 2 poles (-5.933, 19.8127) (-6.1231, 19.8127) (-6.3595, 19.6252) (-6.4186, 19.4223) knots 0 0 0 1 2 2 2
  spline S201 degree 2 poles (-6.4186, 19.4223) (-6.4597, 19.2758) (-6.5162, 19.0318) (-6.5624, 18.8494) knots 0 0 0 1 2 2 2
  spline S202 degree 2 poles (-6.5624, 18.8494) (-6.6061, 18.685) (-6.7371, 18.4255) (-6.8424, 18.3253) knots 0 0 0 1 2 2 2
  spline S203 degree 2 poles (-6.8424, 18.3253) (-6.9478, 18.2277) (-7.2303, 18.1198) (-7.4153, 18.1198) knots 0 0 0 1 2 2 2
  spline S204 degree 2 poles (-7.4153, 18.1198) (-7.8006, 18.1198) (-8.3221, 18.7209) (-8.3221, 19.1859) knots 0 0 0 1 2 2 2
  spline S205 degree 2 poles (-8.3221, 19.1859) (-8.3221, 19.4531) (-8.2168, 19.9258) (-8.1166, 20.1287) knots 0 0 0 1 2 2 2
  line L173 (-8.1166, 20.1287) -> (-7.6131, 20.1287)
  line L174 (-7.6131, 20.1287) -> (-7.6131, 20.0979)
  spline S206 degree 2 poles (-7.6131, 20.0979) (-7.7518, 19.9463) (-7.9573, 19.4736) (-7.9573, 19.2142) knots 0 0 0 1 2 2 2
  spline S207 degree 2 poles (-7.9573, 19.2142) (-7.9573, 18.9213) (-7.6825, 18.5591) (-7.459, 18.5591) knots 0 0 0 1 2 2 2
  spline S208 degree 2 poles (-7.459, 18.5591) (-7.2586, 18.5591) (-7.0197, 18.7723) (-6.9657, 18.9727) knots 0 0 0 1 2 2 2
  spline S209 degree 2 poles (-6.9657, 18.9727) (-6.9298, 19.1063) (-6.8373, 19.4942) (-6.7988, 19.6226) knots 0 0 0 1 2 2 2
  spline S210 degree 2 poles (-6.7988, 19.6226) (-6.6986, 19.9489) (-6.2953, 20.252) (-5.9998, 20.252) knots 0 0 0 1 2 2 2
  spline S211 degree 2 poles (-5.9998, 20.252) (-5.8123, 20.252) (-5.4527, 20.1004) (-5.3268, 19.9643) knots 0 0 0 1 2 2 2
  spline S212 degree 2 poles (-5.3268, 19.9643) (-5.1881, 19.8127) (-5.0391, 19.4274) (-5.0391, 19.1371) knots 0 0 0 1 2 2 2
  spline S213 degree 2 poles (-5.3473, 21.9757) (-5.3114, 21.9269) (-5.1829, 21.7625) (-5.1444, 21.6854) knots 0 0 0 1 2 2 2
  spline S214 degree 2 poles (-5.1444, 21.6854) (-5.0879, 21.5801) (-5.0288, 21.3823) (-5.0288, 21.2025) knots 0 0 0 1 2 2 2
  spline S215 degree 2 poles (-5.0288, 21.2025) (-5.0288, 21.0561) (-5.1393, 20.7915) (-5.2395, 20.6913) knots 0 0 0 1 2 2 2
  spline S216 degree 2 poles (-5.2395, 20.6913) (-5.3371, 20.5962) (-5.6248, 20.4806) (-5.7841, 20.4806) knots 0 0 0 1 2 2 2
  spline S217 degree 2 poles (-5.7841, 20.4806) (-6.0307, 20.4806) (-6.38, 20.6887) (-6.4802, 20.9148) knots 0 0 0 1 2 2 2
  spline S218 degree 2 poles (-6.4802, 20.9148) (-6.5727, 21.1151) (-6.6421, 21.6597) (-6.66, 21.9757) knots 0 0 0 1 2 2 2
  line L175 (-6.66, 21.9757) -> (-6.7371, 21.9757)
  spline S219 degree 2 poles (-6.7371, 21.9757) (-6.8758, 21.9757) (-7.0479, 21.8909) (-7.0968, 21.8139) knots 0 0 0 1 2 2 2
  spline S220 degree 2 poles (-7.0968, 21.8139) (-7.1456, 21.7368) (-7.1764, 21.5159) (-7.1764, 21.3977) knots 0 0 0 1 2 2 2
  spline S221 degree 2 poles (-7.1764, 21.3977) (-7.1764, 21.259) (-7.0942, 20.8839) (-7.0145, 20.6964) knots 0 0 0 1 2 2 2
  line L176 (-7.0145, 20.6964) -> (-7.0145, 20.6733)
  line L177 (-7.0145, 20.6733) -> (-7.423, 20.6733)
  spline S222 degree 2 poles (-7.423, 20.6733) (-7.4538, 20.7838) (-7.5309, 21.1974) (-7.5309, 21.4003) knots 0 0 0 1 2 2 2
  spline S223 degree 2 poles (-7.5309, 21.4003) (-7.5309, 21.6469) (-7.4538, 21.9834) (-7.3536, 22.117) knots 0 0 0 1 2 2 2
  spline S224 degree 2 poles (-7.3536, 22.117) (-7.256, 22.248) (-6.9452, 22.3765) (-6.7217, 22.3765) knots 0 0 0 1 2 2 2
  line L178 (-6.7217, 22.3765) -> (-5.0956, 22.3765)
  line L179 (-5.0956, 22.3765) -> (-5.0956, 21.9757)
  line L180 (-5.0956, 21.9757) -> (-5.3473, 21.9757)
  line L181 (-5.6813, 21.9757) -> (-6.3415, 21.9757)
  spline S225 degree 2 poles (-6.3415, 21.9757) (-6.3287, 21.8319) (-6.285, 21.3977) (-6.2439, 21.2616) knots 0 0 0 1 2 2 2
  spline S226 degree 2 poles (-6.2439, 21.2616) (-6.1951, 21.1023) (-5.9921, 20.8942) (-5.8123, 20.8942) knots 0 0 0 1 2 2 2
  spline S227 degree 2 poles (-5.8123, 20.8942) (-5.6068, 20.8942) (-5.3987, 21.1254) (-5.3987, 21.3463) knots 0 0 0 1 2 2 2
  spline S228 degree 2 poles (-5.3987, 21.3463) (-5.3987, 21.5339) (-5.5606, 21.8421) (-5.6813, 21.9757) knots 0 0 0 1 2 2 2
  line L182 (-5.0956, 24.8066) -> (-5.0956, 24.4059)
  line L183 (-5.0956, 24.4059) -> (-6.452, 24.4059)
  spline S229 degree 2 poles (-6.452, 24.4059) (-6.6164, 24.4059) (-6.8989, 24.3751) (-6.9837, 24.3288) knots 0 0 0 1 2 2 2
  spline S230 degree 2 poles (-6.9837, 24.3288) (-7.0736, 24.28) (-7.161, 24.1053) (-7.161, 23.9563) knots 0 0 0 1 2 2 2
  spline S231 degree 2 poles (-7.161, 23.9563) (-7.161, 23.8073) (-7.0017, 23.4914) (-6.8733, 23.3398) knots 0 0 0 1 2 2 2
  line L184 (-6.8733, 23.3398) -> (-5.0956, 23.3398)
  line L185 (-5.0956, 23.3398) -> (-5.0956, 22.9391)
  line L186 (-5.0956, 22.9391) -> (-7.4744, 22.9391)
  line L187 (-7.4744, 22.9391) -> (-7.4744, 23.3398)
  line L188 (-7.4744, 23.3398) -> (-7.2098, 23.3398)
  spline S232 degree 2 poles (-7.2098, 23.3398) (-7.3716, 23.5196) (-7.5412, 23.8664) (-7.5412, 24.0617) knots 0 0 0 1 2 2 2
  spline S233 degree 2 poles (-7.5412, 24.0617) (-7.5412, 24.411) (-7.0788, 24.8066) (-6.6395, 24.8066) knots 0 0 0 1 2 2 2
  line L189 (-6.6395, 24.8066) -> (-5.0956, 24.8066)
  line L190 (-5.0956, 25.7777) -> (-5.0956, 25.3769)
  line L191 (-5.0956, 25.3769) -> (-7.4744, 25.3769)
  line L192 (-7.4744, 25.3769) -> (-7.4744, 25.7777)
  line L193 (-7.4744, 25.7777) -> (-5.0956, 25.7777)
  line L194 (-7.87, 25.8059) -> (-7.87, 25.3512)
  line L195 (-7.87, 25.3512) -> (-8.2861, 25.3512)
  line L196 (-8.2861, 25.3512) -> (-8.2861, 25.8059)
  line L197 (-8.2861, 25.8059) -> (-7.87, 25.8059)
  spline S234 degree 2 poles (-5.0416, 27.3113) (-5.0416, 27.0647) (-5.1932, 26.6562) (-5.3473, 26.5098) knots 0 0 0 1 2 2 2
  spline S235 degree 2 poles (-5.3473, 26.5098) (-5.4989, 26.3634) (-5.9664, 26.2015) (-6.2798, 26.2015) knots 0 0 0 1 2 2 2
  spline S236 degree 2 poles (-6.2798, 26.2015) (-6.5933, 26.2015) (-7.0505, 26.3685) (-7.2046, 26.5098) knots 0 0 0 1 2 2 2
  spline S237 degree 2 poles (-7.2046, 26.5098) (-7.3613, 26.6511) (-7.5283, 27.0698) (-7.5283, 27.3113) knots 0 0 0 1 2 2 2
  spline S238 degree 2 poles (-7.5283, 27.3113) (-7.5283, 27.5065) (-7.4179, 27.8713) (-7.3459, 28.0126) knots 0 0 0 1 2 2 2
  line L198 (-7.3459, 28.0126) -> (-6.8964, 28.0126)
  line L199 (-6.8964, 28.0126) -> (-6.8964, 27.9895)
  spline S239 degree 2 poles (-6.8964, 27.9895) (-6.9323, 27.9458) (-7.0248, 27.8122) (-7.0736, 27.7172) knots 0 0 0 1 2 2 2
  spline S240 degree 2 poles (-7.0736, 27.7172) (-7.1147, 27.6324) (-7.179, 27.4063) (-7.179, 27.3036) knots 0 0 0 1 2 2 2
  spline S241 degree 2 poles (-7.179, 27.3036) (-7.179, 26.9927) (-6.7089, 26.6151) (-6.2798, 26.6151) knots 0 0 0 1 2 2 2
  spline S242 degree 2 poles (-6.2798, 26.6151) (-5.8611, 26.6151) (-5.391, 26.9799) (-5.391, 27.3036) knots 0 0 0 1 2 2 2
  spline S243 degree 2 poles (-5.391, 27.3036) (-5.391, 27.4988) (-5.5529, 27.8533) (-5.6787, 27.9895) knots 0 0 0 1 2 2 2
  line L200 (-5.6787, 27.9895) -> (-5.6787, 28.0126)
  line L201 (-5.6787, 28.0126) -> (-5.2292, 28.0126)
  spline S244 degree 2 poles (-5.2292, 28.0126) (-5.2009, 27.9535) (-5.1213, 27.7737) (-5.1033, 27.7018) knots 0 0 0 1 2 2 2
  spline S245 degree 2 poles (-5.1033, 27.7018) (-5.0725, 27.599) (-5.0416, 27.4372) (-5.0416, 27.3113) knots 0 0 0 1 2 2 2
  spline S246 degree 2 poles (-5.0391, 30.6534) (-5.0391, 30.3092) (-5.1829, 29.8262) (-5.2857, 29.613) knots 0 0 0 1 2 2 2
  line L202 (-5.2857, 29.613) -> (-5.8149, 29.613)
  line L203 (-5.8149, 29.613) -> (-5.8149, 29.6438)
  spline S247 degree 2 poles (-5.8149, 29.6438) (-5.6196, 29.8519) (-5.4039, 30.3785) (-5.4039, 30.6226) knots 0 0 0 1 2 2 2
  spline S248 degree 2 poles (-5.4039, 30.6226) (-5.4039, 30.9719) (-5.6941, 31.329) (-5.933, 31.329) knots 0 0 0 1 2 2 2
  spline S249 degree 2 poles (-5.933, 31.329) (-6.1231, 31.329) (-6.3595, 31.1415) (-6.4186, 30.9386) knots 0 0 0 1 2 2 2
  spline S250 degree 2 poles (-6.4186, 30.9386) (-6.4597, 30.7921) (-6.5162, 30.5481) (-6.5624, 30.3657) knots 0 0 0 1 2 2 2
  spline S251 degree 2 poles (-6.5624, 30.3657) (-6.6061, 30.2013) (-6.7371, 29.9418) (-6.8424, 29.8416) knots 0 0 0 1 2 2 2
  spline S252 degree 2 poles (-6.8424, 29.8416) (-6.9478, 29.744) (-7.2303, 29.6361) (-7.4153, 29.6361) knots 0 0 0 1 2 2 2
  spline S253 degree 2 poles (-7.4153, 29.6361) (-7.8006, 29.6361) (-8.3221, 30.2372) (-8.3221, 30.7022) knots 0 0 0 1 2 2 2
  spline S254 degree 2 poles (-8.3221, 30.7022) (-8.3221, 30.9694) (-8.2168, 31.4421) (-8.1166, 31.645) knots 0 0 0 1 2 2 2
  line L204 (-8.1166, 31.645) -> (-7.6131, 31.645)
  line L205 (-7.6131, 31.645) -> (-7.6131, 31.6142)
  spline S255 degree 2 poles (-7.6131, 31.6142) (-7.7518, 31.4626) (-7.9573, 30.9899) (-7.9573, 30.7305) knots 0 0 0 1 2 2 2
  spline S256 degree 2 poles (-7.9573, 30.7305) (-7.9573, 30.4376) (-7.6825, 30.0754) (-7.459, 30.0754) knots 0 0 0 1 2 2 2